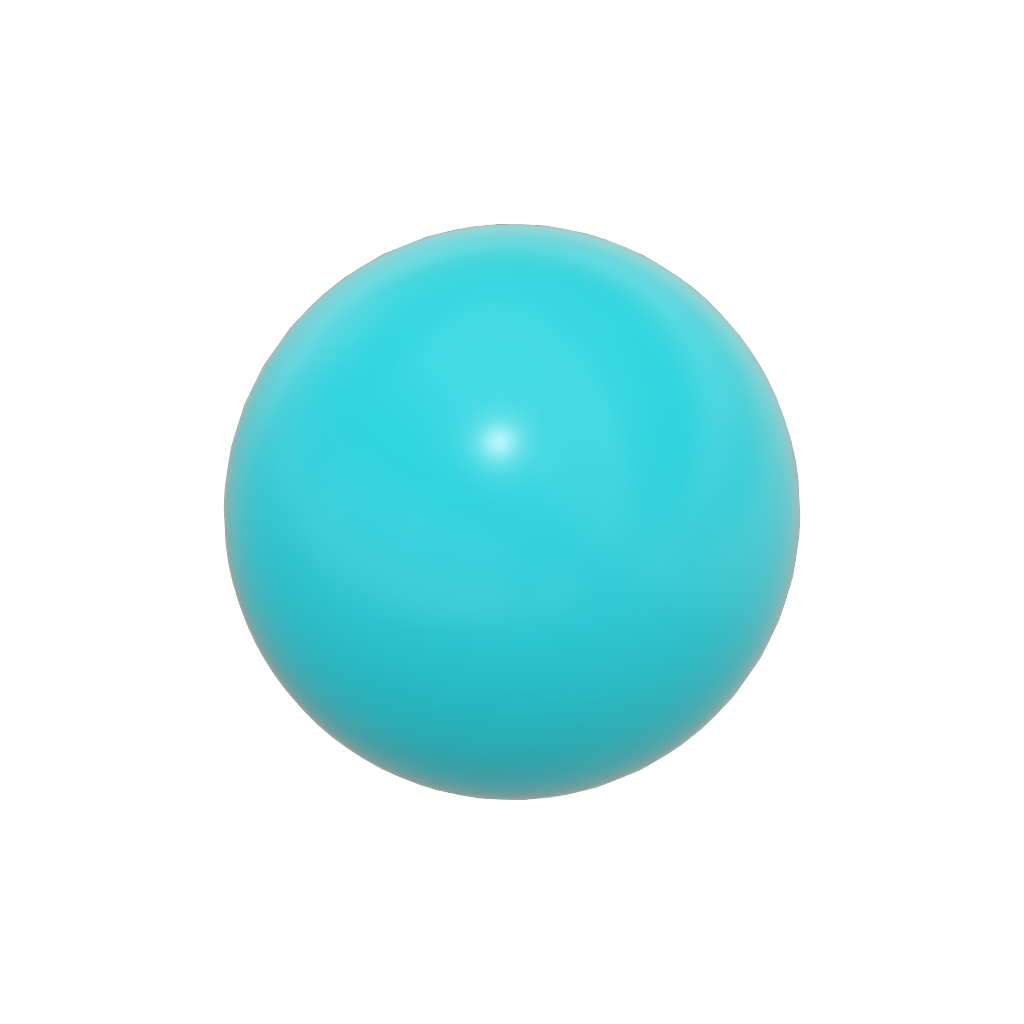
level -1 sphere (Autodesk Fusion 360 design; units mm, degrees)
part number: 2026-10-11-10-53-19-985
Autodesk Fusion 360 part; units mm, degrees
sphere "SpherePrimitive1" add diameter 100 placed x (1, 0, 0) y (0, 0, -1) z (0, 1, 0) at (0, 0, 0)
